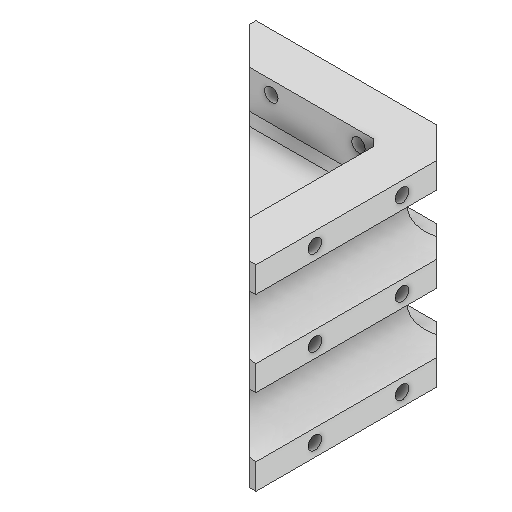
# Autodesk Inventor part: 3DP_PLA_Fiberglass_Pipe_Corner_Bracket
Saved by Autodesk Inventor 2027 (Build 310192060, 192F)
## iProperties
Created: 2026-01-07
Part Number: 3DP_PLA_Fiberglass_Pipe_Corner_Bracket
Material: Generic
Document SubType Name: Modeling
Designer: User
Density: 1 g/cm^3
Appearance: Default
Author: User
Autodesk Inventor part; units mm, degrees
ref_plane "YZ Plane" through (0, 0, 0) normal (1, 0, 0) x (0, 1, 0)
sketch "Sketch1" plane through (0, 0, 0) normal (0, 1, 0) x (-1, 0, 0)
  line L0 (0, 0) -> (100, 0)
  line L1 (0, 0) -> (0, 100)
  line L2 (100, 0) -> (0, 100)
  dimension "d0" = 100
  dimension "d1" = 100
  constraints: 6 end point
  measures "d0" distance of L0.start L1.end
  measures "d1" distance of L0.start L0.end
extrude "Extrusion1" add sketch "Sketch1" along normal blind 90
sketch "Sketch2" plane through (0, 0, 100) normal (1, 0, 0) x (0, 0, -1)
  line L0 (0, 0) -> (100, 0) projected
  line L1 (100, 0) -> (100, 90) projected
  line L2 (0, 90) -> (100, 90) projected
  line L3 (0, 0) -> (0, 90) projected
  circle A0 centre (100, 64.5) radius 13.75
  circle A1 centre (100, 25.5) radius 13.75
  dimension "d4" = 27.5
  dimension "d5" = 27.5
  dimension "d6" = 90
  dimension "d7" = 39
  dimension "d8" = 25.5
  constraints: 2 centre point, 2 point on line
  measures "d4" diameter of A0
  measures "d5" diameter of A1
  measures "d6" distance between parallel lines of L0 L2
  measures "d7" distance of A1.centre A0.centre
  measures "d8" distance from line of L2 A0.centre
extrude "Extrusion2" cut sketch "Sketch2" against normal through all contours A1 L1 | L1 A1 | A0 L1 | L1 A0
sketch "Sketch3" plane through (0, 90, 0) normal (0, 0, -1) x (-1, 0, 0)
  line L0 (0, -90) -> (0, 0) projected
  circle A0 centre (0, -25.5) radius 13.75
  circle A1 centre (0, -64.5) radius 13.75
  point P0 (0, -50.75)
  point P1 (0, -78.25)
  dimension "d11" = 90
  dimension "d12" = 27.5
  dimension "d13" = 27.5
  dimension "d14" = 39
  dimension "d15" = 25.5
  constraints: 2 centre point, 2 point on line
  measures "d11" distance of L0.start L0.end
  measures "d12" diameter of A0
  measures "d13" diameter of A1
  measures "d14" distance of A1.centre A0.centre
  measures "d15" distance of A0.centre L0.end
extrude "Extrusion3" cut sketch "Sketch3" against normal through all contours A0 L0 | L0 A0 | L0 A1 picked at (1.9886, -60.3706)
sketch "Sketch4" plane through (0, 90, 0) normal (0, 1, 0) x (1, 0, 0)
  line L0 (-100, 0) -> (0, -100) projected
  line L1 (0, -100) -> (0, 0) projected
  line L2 (0, 0) -> (-100, 0) projected
  line L3 (-20, -80) -> (-20, -20)
  line L4 (-20, -20) -> (-80, -20)
  dimension "d18" = 20
  dimension "d19" = 20
  constraints: 4 end point, 2 point on line, 1 perpendicular, 1 vertical
  measures "d18" distance between parallel lines of L1 L3
  measures "d19" distance between parallel lines of L2 L4
extrude "Extrusion4" cut sketch "Sketch4" against normal blind 90 contours L4 L3 L0
ref_plane "Work Plane1" through (0, 64.5, 0) normal (0, 1, 0) x (1, 0, 0)
sketch "Sketch5" plane through (0, 64.5, 0) normal (0, 1, 0) x (1, 0, 0)
  line L0 (-20, -80) -> (-20, -20) projected
  line L1 (-20, -20) -> (-80, -20) projected
  line L2 (-20, -80) -> (-80, -20)
  point P0 (0, 0)
  constraints: 2 end point
extrude "Extrusion5" add sketch "Sketch5" along normal mid plane 10
ref_plane "Work Plane2" through (0, 45, 0) normal (0, 1, 0) x (1, 0, 0)
mirror "Mirror1" about plane through (0, 45, 0) normal (0, 1, 0) of "Extrusion5"
sketch "Sketch6" plane through (-20, 90, 20) normal (-1, 0, 0) x (0, 0, 1)
  line L0 (80, -11.75) -> (-20, -11.75) projected
  line L1 (-20, -39.25) -> (80, -39.25) projected
  line L2 (80, -50.75) -> (-20, -50.75) projected
  line L3 (-20, -78.25) -> (80, -78.25) projected
  line L4 (60, -90) -> (0, -90) projected
  line L5 (60, -69.5) -> (0, -69.5) projected
  line L6 (0, -69.5) -> (0, -90) projected
  line L7 (60, -90) -> (0, -90) projected
  line L8 (60, -69.5) -> (60, -90) projected
  line L9 (0, -59.5) -> (60, -59.5) projected
  line L10 (60, -30.5) -> (60, -59.5) projected
  line L11 (60, -30.5) -> (0, -30.5) projected
  line L12 (0, -30.5) -> (0, -59.5) projected
  line L13 (0, -20.5) -> (60, -20.5) projected
  line L14 (60, 0) -> (60, -20.5) projected
  line L15 (0, 0) -> (60, 0) projected
  line L16 (0, 0) -> (0, -20.5) projected
  point P0 (-20, -90)
  point P1 (76, -11.75)
  point P2 (76, -39.25)
  point P3 (76, -50.75)
  point P4 (76, -78.25)
  point P5 (50, -84.125)
  point P6 (10, -84.125)
  point P7 (50, -45)
  point P8 (10, -45)
  point P9 (50, -5.875)
  point P10 (10, -5.875)
  dimension "d29" = 11.75
  dimension "d30" = 10
  dimension "d31" = 10
  dimension "d32" = 5.875
  dimension "d33" = 5.875
  dimension "d34" = 11.5
  dimension "d35" = 5.75
  constraints: 4 vertical alignment, 3 horizontal alignment
  measures "d29" distance between parallel lines of L4 L3
  measures "d30" distance from line of L8 point (50, -84.125)
  measures "d31" distance from line of L6 point (10, -84.125)
  measures "d32" distance from line of L4 point (50, -84.125)
  measures "d33" distance from line of L15 point (50, -5.875)
  measures "d34" distance between parallel lines of L2 L1
  measures "d35" distance from line of L1 point (50, -45)
hole "Hole1" at (-20, 5.875, 70) at (-20, 5.875, 30) at (-20, 45, 70) at (-20, 45, 30) at (-20, 84.125, 70) at (-20, 84.125, 30) direction (1, 0, 0) diameter 6.2 end through all
sketch "Sketch7" plane through (-80, 90, 20) normal (0, 0, 1) x (1, 0, 0)
  line L0 (60, -69.5) -> (0, -69.5) projected
  line L1 (0, -90) -> (0, -69.5) projected
  line L2 (60, -90) -> (0, -90) projected
  line L3 (60, -69.5) -> (60, -90) projected
  line L4 (0, -59.5) -> (60, -59.5) projected
  line L5 (60, -30.5) -> (60, -59.5) projected
  line L6 (60, -30.5) -> (0, -30.5) projected
  line L7 (0, -59.5) -> (0, -30.5) projected
  line L8 (0, -20.5) -> (60, -20.5) projected
  line L9 (60, 0) -> (60, -20.5) projected
  line L10 (0, 0) -> (60, 0) projected
  line L11 (0, -20.5) -> (0, 0) projected
  line L12 (80, -11.75) -> (-20, -11.75) projected
  line L13 (-20, -39.25) -> (80, -39.25) projected
  line L14 (80, -50.75) -> (-20, -50.75) projected
  line L15 (-20, -78.25) -> (80, -78.25) projected
  point P0 (80, -90)
  point P1 (-16, -11.75)
  point P2 (-16, -39.25)
  point P3 (-16, -50.75)
  point P4 (-16, -78.25)
  point P5 (50, -84.125)
  point P6 (10, -84.125)
  point P7 (10, -45)
  point P8 (50, -45)
  point P9 (10, -5.875)
  point P10 (50, -5.875)
  dimension "d43" = 11.75
  dimension "d44" = 11.5
  dimension "d45" = 11.75
  dimension "d46" = 10
  dimension "d47" = 10
  dimension "d48" = 5.875
  dimension "d49" = 5.875
  dimension "d50" = 5.75
  constraints: 4 vertical alignment, 3 horizontal alignment
  measures "d43" distance between parallel lines of L15 L2
  measures "d44" distance between parallel lines of L13 L14
  measures "d45" distance between parallel lines of L10 L12
  measures "d46" distance from line of L1 point (10, -84.125)
  measures "d47" distance from line of L3 point (50, -84.125)
  measures "d48" distance from line of point (10, -84.125) L2
  measures "d49" distance from line of L10 point (10, -5.875)
  measures "d50" distance from line of L13 point (10, -45)
hole "Hole2" at (-30, 5.875, 20) at (-70, 5.875, 20) at (-70, 45, 20) at (-30, 45, 20) at (-70, 84.125, 20) at (-30, 84.125, 20) direction (0, 0, -1) diameter 6.2 end through all
chamfer "Chamfer2" distance 14 angle 45 3 edges at (0, 5.875, 0) (0, 45, 0) (0, 84.125, 0)
sketch "Sketch8" plane through (0, 90, 0) normal (0, 1, 0) x (1, 0, 0)
  line L0 (0, -100) -> (0, -14) projected
  line L1 (-14, 0) -> (-100, 0) projected
  line L2 (0, -97) -> (-97, -97)
  line L3 (-97, -97) -> (-97, 0)
  line L4 (-97, 0) -> (0, 0)
  line L5 (0, 0) -> (0, -97)
  dimension "d61" = 3
  dimension "d62" = 3
  constraints: 8 end point, 2 parallel, 2 point on line, 1 horizontal, 1 perpendicular
  measures "d61" distance from line of L0.start L2
  measures "d62" distance from line of L1.end L3
extrude "Extrusion6" cut sketch "Sketch8" against normal through all keep common part
chamfer "Chamfer3" distance 3 angle 45 8 edges at (-20, 59.5, 50) (-50, 59.5, 20) (-20, 69.5, 50) (-50, 69.5, 20) (-20, 30.5, 50) (-50, 30.5, 20) (-50, 20.5, 20) (-20, 20.5, 50)
chamfer "Chamfer4" distance 3 angle 45 3 edges at (-20, 81.25, 20) (-20, 45, 20) (-20, 8.75, 20)
equation "\"d0\" = d1"
equation "\"d8\" = -0.5 * d7 + 0.5 * d6"
equation "\"d15\" = -0.5 * d14 + 0.5 * d11"
equation "\"d19\" = d18"
equation "\"d31\" = d30"
equation "\"d32\" = 0.5 * d29"
equation "\"d33\" = d32"
equation "\"d35\" = 0.5 * d34"
equation "\"d47\" = d46"
equation "\"d48\" = 0.5 * d43"
equation "\"d49\" = 0.5 * d45"
equation "\"d50\" = 0.5 * d44"
equation "\"d62\" = d61"
body "Solid1"
